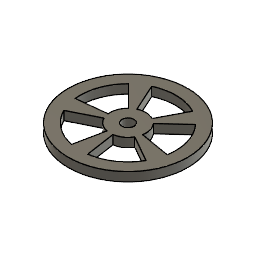
SpokeWheel (Autodesk Fusion 360 design; units mm, degrees)
part number: 2026-08-28-14-11-31-386
Autodesk Fusion 360 part; units mm, degrees
sketch "Sketch1" plane through (0, 0, 0) normal (0, 1, 0) x (1, 0, 0)
  circle A0 centre (0, 0) radius 100
  dimension "d1" = 200
  constraint coincident A0.centre origin
  measures "d1" diameter of A0
extrude "Extrude1" add sketch "Sketch1" along normal blind 15
hole "Hole2" at (0, 15, 0) direction (0, -1, 0) diameter 20 end through all
sketch "Sketch2" plane through (0, 15, 0) normal (0, 1, 0) x (-1, 0, 0)
  circle A0 centre (0, 0) radius 10
  circle A1 centre (0, 0) radius 100
  circle A2 centre (0, 0) radius 30 construction
  circle A3 centre (0, 0) radius 80 construction
  line L0 (12.4053, -27.315) -> (33.0809, -72.8399)
  line L1 (33.0809, -72.8399) -> (12.4053, -27.315)
  line L2 (-37.032, -70.9128) -> (-13.887, -26.5923)
  line L3 (-13.887, -26.5923) -> (-37.032, -70.9128)
  arc A4 (-13.887, -26.5923) -> (12.4053, -27.315) centre (0, 0) ccw
  arc A5 (-37.032, -70.9128) -> (33.0809, -72.8399) centre (0, 0) ccw
  dimension "d8" = 60
  dimension "d9" = 160
  constraint concentric A0 A2
  constraint concentric A0 A3
  constraint coincident A3 L2.start
  constraint coincident A3 L0.end
  constraint coincident A2 L0.start
  constraint coincident A2 L2.end
  measures "d8" diameter of A2
  measures "d9" diameter of A3
extrude "Extrude2" cut sketch "Sketch2" against normal through all contours L0 L1 L2 L3 A4 A5
pattern_circular "C-Pattern1" count 5 over 360 about axis through (0, 15, 0) along (0, -1, 0) of "Extrude2"
